Autodesk Fusion 360 part; units mm, degrees
(part 2 of 2)
sketch "Slide switch sketch" plane through (0, 0, 0) normal (0, 0, 1) x (1, 0, 0) in component "Reference electronics (not printed)"
  line L0 (77.7, 60.2) -> (86.3, 60.2)
  line L1 (86.3, 60.2) -> (86.3, 63.8)
  line L2 (86.3, 63.8) -> (77.7, 63.8)
  line L3 (77.7, 63.8) -> (77.7, 60.2)
  dimension "d577" = 8.6
  dimension "d578" = 3.6
  dimension "d579" = 77.7
  dimension "d580" = 60.2
  measures "d577" horizontal distance of L0.start L0.end
  measures "d578" vertical distance of L0.start L2.end
  measures "d579" horizontal distance of origin L0.start
  measures "d580" vertical distance of origin L0.start
extrude "Slide switch" add sketch "Slide switch sketch" along normal blind 3.6 from surface at 5.8 separate body makes body 23 in component "Reference electronics (not printed)"
sketch "Battery divider sketch" plane through (0, 0, 0) normal (0, 0, 1) x (1, 0, 0) in component "Frame"
  line L0 (44.3, 1.7) -> (45.5, 1.7)
  line L1 (45.5, 1.7) -> (45.5, 54.6)
  line L2 (45.5, 54.6) -> (44.3, 54.6)
  line L3 (44.3, 54.6) -> (44.3, 1.7)
  dimension "d584" = 1.2
  dimension "d585" = 52.9
  dimension "d586" = 44.3
  dimension "d587" = 1.7
  measures "d584" horizontal distance of L0.start L0.end
  measures "d585" vertical distance of L0.start L2.end
  measures "d586" horizontal distance of origin L0.start
  measures "d587" vertical distance of origin L0.start
extrude "Battery divider" add sketch "Battery divider sketch" along normal blind 12 from surface at 1.6 bodies 1 in component "Frame"
component "Frame" placed x (1, 0, 0) y (0, 1, 0) z (0, 0, 1) at (0, 0, 0)
component "Back plate (clear)" placed x (1, 0, 0) y (0, 1, 0) z (0, 0, 1) at (0, 0, 0)
component "Front plate (clear)" placed x (1, 0, 0) y (0, 1, 0) z (0, 0, 1) at (0, 0, 0)
component "Lens ring" placed x (1, 0, 0) y (0, 1, 0) z (0, 0, 1) at (0, 0, 0)
component "Viewfinder trims" placed x (1, 0, 0) y (0, 1, 0) z (0, 0, 1) at (0, 0, 0)
component "Button caps" placed x (1, 0, 0) y (0, 1, 0) z (0, 0, 1) at (0, 0, 0)
component "Shutter cap" placed x (1, 0, 0) y (0, 1, 0) z (0, 0, 1) at (0, 0, 0)
component "Reference electronics (not printed)" placed x (1, 0, 0) y (0, 1, 0) z (0, 0, 1) at (0, 0, 0)
equation "body_W = 116 mm" comment "Body width, seen from the back"
equation "body_H = 66 mm" comment "Body height"
equation "corner_R = 7 mm" comment "Outer corner radius"
equation "wall = 2.2 mm" comment "Frame wall thickness"
equation "plate_t = 1.6 mm" comment "Clear plate thickness, front and back"
equation "cav = 12 mm" comment "Inside depth = frame thickness"
equation "clr = 0.3 mm" comment "Fit clearance"
equation "screw_inset = 5 mm" comment "Corner screw centres from the edges"
equation "screw4_x = 17 mm" comment "Top-left screw x, moved in for the keychain"
equation "boss_r = 3.2 mm" comment "Screw post radius"
equation "insert_d = 3.2 mm" comment "M2 heat-set insert hole"
equation "insert_len = 3.5 mm" comment "Insert hole depth, each face"
equation "pilot_d = 1.8 mm" comment "Hole through the posts"
equation "screw_clear = 2.4 mm" comment "Screw clearance in the plates"
equation "key_d = 4.2 mm" comment "Keychain hole"
equation "key_inset = 6 mm" comment "Keychain hole centre from the top-left edges"
equation "key_block = 11 mm" comment "Solid corner around the keychain hole"
equation "bat_L = 35 mm" comment "Battery width: 103450 plus allowance"
equation "bat_H = 52 mm" comment "Battery length incl. protection board"
equation "bat_T = 10.5 mm" comment "Battery thickness"
equation "bat_x = 9 mm" comment "Battery left edge"
equation "bat_y = 2.6 mm" comment "Battery bottom edge"
equation "board_L = 67 mm" comment "GOOUUU board length (MEASURE)"
equation "board_W = 28 mm" comment "GOOUUU board width (MEASURE)"
equation "board_T = 7 mm" comment "Board height, headers removed (MEASURE)"
equation "board_x = 46 mm" comment "Board left edge"
equation "board_y = 8.5 mm" comment "Board bottom edge"
equation "usb_y = 22 mm" comment "Board USB-C centre height on the right wall (MEASURE)"
equation "scr_W = 58 mm" comment "2.0 in screen module width (MEASURE)"
equation "scr_H = 35 mm" comment "Screen module height (MEASURE)"
equation "scr_T = 4.5 mm" comment "Screen module thickness (MEASURE)"
equation "scr_aW = 40.8 mm" comment "Screen active area width"
equation "scr_aH = 30.6 mm" comment "Screen active area height"
equation "scr_x = body_W - screw_inset - boss_r - 0.6 mm - scr_W" comment "Screen module left edge, clear of the corner post"
equation "scr_y = 3 mm" comment "Screen module bottom edge"
equation "chg_L = 18 mm" comment "Charge module length"
equation "chg_W = 14 mm" comment "Charge module width (USB-C edge)"
equation "chg_T = 4 mm" comment "Charge module thickness"
equation "chg_x = body_W - wall - chg_L - clr" comment "Charge module left edge"
equation "chg_y = 38.5 mm" comment "Charge module bottom edge"
equation "cam_S = 8.5 mm" comment "Camera module size (MEASURE)"
equation "cam_T = 5.5 mm" comment "Camera module thickness with lens (MEASURE)"
equation "lens_d = 8 mm" comment "Lens barrel diameter (MEASURE)"
equation "lens_x = 72 mm" comment "Lens centre x"
equation "lens_y = 51 mm" comment "Lens centre y"
equation "vf_W = 16 mm" comment "Viewfinder window width"
equation "vf_H = 12 mm" comment "Viewfinder window height"
equation "vf_x = 48 mm" comment "Viewfinder left edge"
equation "vf_y = 45 mm" comment "Viewfinder bottom edge"
equation "vf_wall = 1.2 mm" comment "Viewfinder tube wall"
equation "vf_r = 1.6 mm" comment "Viewfinder window corner radius"
equation "btn_x1 = 84 mm" comment "First back button centre (prev)"
equation "btn_pitch = 12 mm" comment "Back button spacing"
equation "btn_y = 50 mm" comment "Back button centre height"
equation "btn_S = 6 mm" comment "Tactile switch body"
equation "btn_T = 5 mm" comment "Tactile switch height incl. plunger"
equation "btn_body_T = 3.5 mm" comment "Tactile switch body height"
equation "cap_d = 6 mm" comment "Button cap shaft"
equation "cap_flange_d = 8.4 mm" comment "Button cap flange"
equation "cap_flange_t = 1 mm" comment "Button cap flange thickness"
equation "cap_proud = 1.2 mm" comment "Cap height above the back plate"
equation "shelf_t = 1.6 mm" comment "Internal shelves"
equation "btn_shelf_z = plate_t + cap_flange_t + btn_T" comment "Button shelf height"
equation "shutter_x = 100 mm" comment "Shutter centre x"
equation "shutter_cap_d = 8 mm" comment "Shutter cap diameter"
equation "sw_x = 82 mm" comment "Power switch centre x"
equation "sw_L = 8.6 mm" comment "Slide switch body length"
equation "sw_W = 3.6 mm" comment "Slide switch body depth"
equation "sw_T = 3.6 mm" comment "Slide switch body height"
equation "sw_knob_W = 2 mm" comment "Slide switch knob width"
equation "sw_knob_T = 1.5 mm" comment "Slide switch knob height"
equation "sw_travel = 2 mm" comment "Slide switch knob travel"
equation "d73 = body_W"
equation "d74 = body_H"
equation "d75 = plate_t"
equation "d76 = cav"
equation "d79 = corner_R"
equation "d80 = body_W - 2 * wall"
equation "d81 = body_H - 2 * wall"
equation "d82 = wall"
equation "d83 = wall"
equation "d84 = plate_t - 1 mm"
equation "d85 = cav + 2 mm"
equation "d88 = corner_R - wall"
equation "d89 = 2 * boss_r"
equation "d90 = screw_inset"
equation "d91 = screw_inset"
equation "d92 = 2 * boss_r"
equation "d93 = body_W - screw_inset"
equation "d94 = 2 * boss_r"
equation "d95 = body_H - screw_inset"
equation "d96 = 2 * boss_r"
equation "d97 = screw4_x"
equation "d98 = plate_t"
equation "d99 = cav"
equation "d101 = key_block - wall"
equation "d102 = key_block - wall"
equation "d103 = wall"
equation "d104 = body_H - key_block"
equation "d105 = plate_t"
equation "d106 = cav"
equation "d108 = vf_W + 2 * vf_wall"
equation "d109 = vf_H + 2 * vf_wall"
equation "d110 = vf_x - vf_wall"
equation "d111 = vf_y - vf_wall"
equation "d112 = plate_t"
equation "d113 = cav"
equation "d116 = body_H - wall - vf_y - vf_H + 0.5 mm"
equation "d117 = vf_x + vf_W / 2 - 1 mm"
equation "d118 = vf_y + vf_H"
equation "d119 = plate_t"
equation "d120 = cav"
equation "d122 = cam_S + 3.2 mm"
equation "d123 = cam_S + 3.2 mm"
equation "d124 = lens_x - cam_S / 2 - 1.6 mm"
equation "d125 = lens_y - cam_S / 2 - 1.6 mm"
equation "d126 = plate_t + cav - cam_T - 1.2 mm"
equation "d127 = cam_T + 1.2 mm"
equation "d130 = body_H - wall - lens_y - cam_S / 2 + 0.5 mm"
equation "d131 = lens_x - 1.5 mm"
equation "d132 = lens_y + cam_S / 2"
equation "d133 = plate_t + cav - cam_T - 1.2 mm"
equation "d134 = cam_T + 1.2 mm"
equation "d136 = body_W - wall - btn_x1 + 5.5 mm"
equation "d138 = btn_x1 - 5 mm"
equation "d139 = btn_y - 6 mm"
equation "d140 = btn_shelf_z"
equation "d141 = shelf_t"
equation "d143 = body_W - wall - shutter_x + 5.5 mm"
equation "d144 = shelf_t"
equation "d145 = shutter_x - 5 mm"
equation "d146 = body_H - wall - 1 mm - btn_T - shelf_t"
equation "d147 = plate_t + cav / 2 - 5 mm"
equation "d150 = sw_L + 2.4 mm"
equation "d151 = sw_W + 1.7 mm"
equation "d152 = sw_x - sw_L / 2 - 1.2 mm"
equation "d153 = body_H - wall - sw_W - 1.2 mm"
equation "d154 = plate_t + cav / 2 - sw_T / 2 - 1.2 mm"
equation "d155 = sw_T + 2.4 mm"
equation "d167 = insert_d"
equation "d168 = screw_inset"
equation "d169 = screw_inset"
equation "d170 = insert_d"
equation "d171 = body_W - screw_inset"
equation "d172 = insert_d"
equation "d173 = body_H - screw_inset"
equation "d174 = insert_d"
equation "d175 = screw4_x"
equation "d176 = plate_t - 1 mm"
equation "d177 = insert_len + 1 mm"
equation "d179 = insert_d"
equation "d180 = screw_inset"
equation "d181 = screw_inset"
equation "d182 = insert_d"
equation "d183 = body_W - screw_inset"
equation "d184 = insert_d"
equation "d185 = body_H - screw_inset"
equation "d186 = insert_d"
equation "d187 = screw4_x"
equation "d188 = plate_t + cav - insert_len"
equation "d189 = insert_len + 1 mm"
equation "d191 = pilot_d"
equation "d192 = screw_inset"
equation "d193 = screw_inset"
equation "d194 = pilot_d"
equation "d195 = body_W - screw_inset"
equation "d196 = pilot_d"
equation "d197 = body_H - screw_inset"
equation "d198 = pilot_d"
equation "d199 = screw4_x"
equation "d200 = plate_t - 1 mm"
equation "d201 = cav + 2 mm"
equation "d203 = key_d"
equation "d204 = key_inset"
equation "d205 = body_H - key_inset"
equation "d206 = plate_t - 1 mm"
equation "d207 = cav + 2 mm"
equation "d209 = vf_W"
equation "d210 = vf_H"
equation "d211 = vf_x"
equation "d212 = vf_y"
equation "d213 = plate_t - 1 mm"
equation "d214 = cav + 2 mm"
equation "d216 = cam_S + 2 * clr"
equation "d217 = cam_S + 2 * clr"
equation "d218 = lens_x - cam_S / 2 - clr"
equation "d219 = lens_y - cam_S / 2 - clr"
equation "d220 = plate_t + cav - cam_T - clr"
equation "d221 = cam_T + clr + 1 mm"
equation "d225 = lens_x - 4 mm"
equation "d226 = lens_y - cam_S / 2 - 2 mm"
equation "d227 = plate_t + cav - cam_T - 2 mm"
equation "d228 = cam_T + 3 mm"
equation "d230 = btn_S + 2 * clr"
equation "d231 = btn_S + 2 * clr"
equation "d232 = btn_x1 - btn_S / 2 - clr"
equation "d233 = btn_y - btn_S / 2 - clr"
equation "d234 = btn_S + 2 * clr"
equation "d235 = btn_S + 2 * clr"
equation "d236 = btn_x1 + btn_pitch - btn_S / 2 - clr"
equation "d237 = btn_S + 2 * clr"
equation "d238 = btn_S + 2 * clr"
equation "d239 = btn_x1 + 2 * btn_pitch - btn_S / 2 - clr"
equation "d240 = btn_shelf_z - btn_body_T"
equation "d241 = btn_body_T + 0.01 mm"
equation "d245 = btn_x1 - 1.5 mm"
equation "d246 = btn_y - 3.8 mm"
equation "d249 = btn_x1 + btn_pitch - 1.5 mm"
equation "d252 = btn_x1 + 2 * btn_pitch - 1.5 mm"
equation "d253 = btn_shelf_z - 0.1 mm"
equation "d254 = shelf_t + 0.2 mm"
equation "d256 = sw_L + 2 * clr"
equation "d257 = sw_W + clr + 0.01 mm"
equation "d258 = sw_x - sw_L / 2 - clr"
equation "d259 = body_H - wall - sw_W - clr"
equation "d260 = plate_t + cav / 2 - sw_T / 2 - clr"
equation "d261 = sw_T + 2 * clr"
equation "d263 = sw_knob_W + sw_travel + 0.6 mm"
equation "d264 = wall + 1 mm"
equation "d265 = sw_x - ( sw_knob_W + sw_travel ) / 2 - 0.3 mm"
equation "d266 = body_H - wall - 0.5 mm"
equation "d267 = plate_t + cav / 2 - sw_knob_T / 2 - 0.3 mm"
equation "d268 = sw_knob_T + 0.6 mm"
equation "d272 = sw_x - 6 mm"
equation "d273 = body_H - 1.2 mm"
equation "d274 = plate_t + cav / 2 - 3.5 mm"
equation "d277 = wall + 2 mm"
equation "d279 = body_W - wall - 1 mm"
equation "d280 = chg_y + chg_W / 2 - 5 mm"
equation "d281 = plate_t + cav - chg_T / 2 - 2.2 mm"
equation "d284 = wall + 2 mm"
equation "d286 = body_W - wall - 1 mm"
equation "d287 = usb_y - 5 mm"
equation "d288 = plate_t + cav - 3.2 mm - 2.2 mm"
equation "d291 = body_H - wall - 1 mm"
equation "d293 = shutter_cap_d + 0.4 mm"
equation "d294 = shutter_x"
equation "d295 = plate_t + cav / 2"
equation "d296 = wall + 2 mm"
equation "lens_ring_d = 19 mm" comment "Lens ring outer diameter"
equation "lens_ring_h = 2.4 mm" comment "Lens ring height above the front plate"
equation "vf_trim = 2.4 mm" comment "Viewfinder trim width around the window"
equation "vf_trim_t = 1.2 mm" comment "Viewfinder trim thickness"
equation "shutter_flange = 1.2 mm" comment "Shutter cap flange, beyond the shaft"
equation "shutter_proud = 1 mm" comment "Shutter cap height above the top edge"
equation "d305 = vf_r"
equation "d307 = vf_r + vf_wall"
equation "d308 = body_W"
equation "d309 = body_H"
equation "d311 = plate_t"
equation "d314 = corner_R"
equation "d315 = screw_clear"
equation "d316 = screw_inset"
equation "d317 = screw_inset"
equation "d318 = screw_clear"
equation "d319 = body_W - screw_inset"
equation "d320 = screw_clear"
equation "d321 = body_H - screw_inset"
equation "d322 = screw_clear"
equation "d323 = screw4_x"
equation "d324 = 0 mm - 1 mm"
equation "d325 = plate_t + 2 mm"
equation "d327 = key_d"
equation "d328 = key_inset"
equation "d329 = body_H - key_inset"
equation "d330 = 0 mm - 1 mm"
equation "d331 = plate_t + 2 mm"
equation "d333 = vf_W"
equation "d334 = vf_H"
equation "d335 = vf_x"
equation "d336 = vf_y"
equation "d337 = 0 mm - 1 mm"
equation "d338 = plate_t + 2 mm"
equation "d340 = 0 mm - 1 mm"
equation "d341 = plate_t + 2 mm"
equation "d344 = vf_r"
equation "d345 = scr_aW + 0.6 mm"
equation "d346 = scr_aH + 0.6 mm"
equation "d347 = scr_x + ( scr_W - scr_aW ) / 2 - 0.3 mm"
equation "d348 = scr_y + ( scr_H - scr_aH ) / 2 - 0.3 mm"
equation "d349 = 0 mm - 1 mm"
equation "d350 = plate_t + 2 mm"
equation "d352 = cap_d + 0.4 mm"
equation "d353 = btn_x1"
equation "d354 = btn_y"
equation "d355 = cap_d + 0.4 mm"
equation "d356 = btn_x1 + btn_pitch"
equation "d357 = cap_d + 0.4 mm"
equation "d358 = btn_x1 + 2 * btn_pitch"
equation "d359 = 0 mm - 1 mm"
equation "d360 = plate_t + 2 mm"
equation "d362 = body_W"
equation "d363 = body_H"
equation "d364 = plate_t + cav"
equation "d365 = plate_t"
equation "d368 = corner_R"
equation "d369 = screw_clear"
equation "d370 = screw_inset"
equation "d371 = screw_inset"
equation "d372 = screw_clear"
equation "d373 = body_W - screw_inset"
equation "d374 = screw_clear"
equation "d375 = body_H - screw_inset"
equation "d376 = screw_clear"
equation "d377 = screw4_x"
equation "d378 = plate_t + cav - 1 mm"
equation "d379 = plate_t + 2 mm"
equation "d381 = key_d"
equation "d382 = key_inset"
equation "d383 = body_H - key_inset"
equation "d384 = plate_t + cav - 1 mm"
equation "d385 = plate_t + 2 mm"
equation "d387 = vf_W"
equation "d388 = vf_H"
equation "d389 = vf_x"
equation "d390 = vf_y"
equation "d391 = plate_t + cav - 1 mm"
equation "d392 = plate_t + 2 mm"
equation "d394 = plate_t + cav - 1 mm"
equation "d395 = plate_t + 2 mm"
equation "d398 = vf_r"
equation "d399 = lens_d + 0.8 mm"
equation "d400 = lens_x"
equation "d401 = lens_y"
equation "d402 = plate_t + cav - 1 mm"
equation "d403 = plate_t + 2 mm"
equation "d405 = lens_ring_d"
equation "d406 = lens_x"
equation "d407 = lens_y"
equation "d408 = lens_d + 1.2 mm"
equation "d409 = plate_t + cav + plate_t"
equation "d410 = lens_ring_h"
equation "d412 = vf_W + 2 * vf_trim"
equation "d413 = vf_H + 2 * vf_trim"
equation "d414 = vf_x - vf_trim"
equation "d415 = vf_y - vf_trim"
equation "d416 = vf_W"
equation "d417 = vf_H"
equation "d418 = vf_x"
equation "d419 = vf_y"
equation "d420 = plate_t + cav + plate_t"
equation "d421 = vf_trim_t"
equation "d424 = vf_r + vf_trim"
equation "d426 = vf_r"
equation "d427 = vf_W + 2 * vf_trim"
equation "d428 = vf_H + 2 * vf_trim"
equation "d429 = vf_x - vf_trim"
equation "d430 = vf_y - vf_trim"
equation "d431 = vf_W"
equation "d432 = vf_H"
equation "d433 = vf_x"
equation "d434 = vf_y"
equation "d435 = -vf_trim_t"
equation "d436 = vf_trim_t"
equation "d439 = vf_r + vf_trim"
equation "d441 = vf_r"
equation "d442 = cap_d"
equation "d443 = btn_x1"
equation "d444 = btn_y"
equation "d445 = -cap_proud"
equation "d446 = plate_t + cap_proud"
equation "d448 = cap_flange_d"
equation "d449 = btn_x1"
equation "d450 = btn_y"
equation "d451 = plate_t"
equation "d452 = cap_flange_t"
equation "d454 = cap_d"
equation "d455 = btn_x1 + btn_pitch"
equation "d456 = btn_y"
equation "d457 = -cap_proud"
equation "d458 = plate_t + cap_proud"
equation "d460 = cap_flange_d"
equation "d461 = btn_x1 + btn_pitch"
equation "d462 = btn_y"
equation "d463 = plate_t"
equation "d464 = cap_flange_t"
equation "d466 = cap_d"
equation "d467 = btn_x1 + 2 * btn_pitch"
equation "d468 = btn_y"
equation "d469 = -cap_proud"
equation "d470 = plate_t + cap_proud"
equation "d472 = cap_flange_d"
equation "d473 = btn_x1 + 2 * btn_pitch"
equation "d474 = btn_y"
equation "d475 = plate_t"
equation "d476 = cap_flange_t"
equation "d478 = ( body_H - wall - 1 mm )"
equation "d480 = shutter_cap_d + 2 * shutter_flange"
equation "d481 = shutter_x"
equation "d482 = plate_t + cav / 2"
equation "d485 = ( body_H - wall )"
equation "d487 = shutter_cap_d"
equation "d488 = shutter_x"
equation "d489 = plate_t + cav / 2"
equation "d490 = wall + shutter_proud"
equation "d493 = shutter_cap_d / 4"
equation "d494 = bat_L"
equation "d495 = bat_H"
equation "d496 = bat_x"
equation "d497 = bat_y"
equation "d498 = plate_t + ( cav - bat_T ) / 2"
equation "d499 = bat_T"
equation "d501 = board_L"
equation "d502 = board_W"
equation "d503 = board_x"
equation "d504 = board_y"
equation "d505 = plate_t + cav - board_T"
equation "d510 = board_x + 6 mm"
equation "d511 = board_y + 4 mm"
equation "d512 = plate_t + cav - board_T + 1.6 mm"
equation "d515 = scr_W"
equation "d516 = scr_H"
equation "d517 = scr_x"
equation "d518 = scr_y"
equation "d519 = plate_t"
equation "d520 = scr_T"
equation "d522 = scr_aW"
equation "d523 = scr_aH"
equation "d524 = scr_x + ( scr_W - scr_aW ) / 2"
equation "d525 = scr_y + ( scr_H - scr_aH ) / 2"
equation "d526 = plate_t - 0.2 mm"
equation "d529 = chg_L"
equation "d530 = chg_W"
equation "d531 = chg_x"
equation "d532 = chg_y"
equation "d533 = plate_t + cav - chg_T"
equation "d534 = chg_T"
equation "d536 = cam_S"
equation "d537 = cam_S"
equation "d538 = lens_x - cam_S / 2"
equation "d539 = lens_y - cam_S / 2"
equation "d540 = plate_t + cav - cam_T"
equation "d541 = cam_T - 3 mm"
equation "d543 = lens_d"
equation "d544 = lens_x"
equation "d545 = lens_y"
equation "d546 = plate_t + cav - cam_T"
equation "d547 = cam_T"
equation "d549 = btn_S"
equation "d550 = btn_S"
equation "d551 = btn_x1 - btn_S / 2"
equation "d552 = btn_y - btn_S / 2"
equation "d553 = btn_shelf_z - btn_body_T"
equation "d554 = btn_body_T"
equation "d556 = btn_S"
equation "d557 = btn_S"
equation "d558 = btn_x1 + btn_pitch - btn_S / 2"
equation "d559 = btn_y - btn_S / 2"
equation "d560 = btn_shelf_z - btn_body_T"
equation "d561 = btn_body_T"
equation "d563 = btn_S"
equation "d564 = btn_S"
equation "d565 = btn_x1 + 2 * btn_pitch - btn_S / 2"
equation "d566 = btn_y - btn_S / 2"
equation "d567 = btn_shelf_z - btn_body_T"
equation "d568 = btn_body_T"
equation "d570 = btn_S"
equation "d571 = btn_body_T"
equation "d572 = shutter_x - btn_S / 2"
equation "d573 = body_H - wall - 1 mm - btn_T"
equation "d574 = plate_t + cav / 2 - btn_S / 2"
equation "d575 = btn_S"
equation "d577 = sw_L"
equation "d578 = sw_W"
equation "d579 = sw_x - sw_L / 2"
equation "d580 = body_H - wall - sw_W"
equation "d581 = plate_t + cav / 2 - sw_T / 2"
equation "d582 = sw_T"
equation "d585 = bat_y + bat_H - wall + 0.5 mm"
equation "d586 = bat_x + bat_L + clr"
equation "d587 = wall - 0.5 mm"
equation "d588 = plate_t"
equation "d589 = cav"
named bodies: "Frame", "Back plate (clear)", "Front plate (clear)", "Lens ring", "Viewfinder trim front", "Viewfinder trim back", "Button cap prev", "Button cap ok", "Button cap next", "Shutter cap", "Battery 103450 2000mAh", "GOOUUU ESP32-S3-CAM board", "Screen module 2.0in", "Screen active area", "Charge-boost module", "OV3660 camera module", "Button switch prev", "Button switch ok", "Button switch next", "Shutter switch", "Slide switch"
